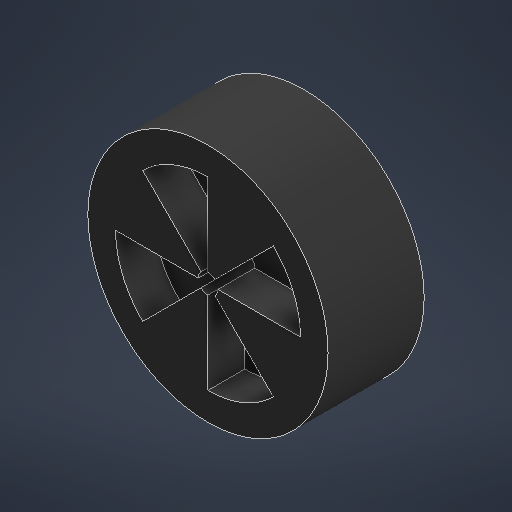
# Autodesk Inventor part: Rueda
Saved by Autodesk Inventor 2026.2 (Build 302298010, 298A)
## iProperties
Created: 2026-10-27
Part Number: Rueda
Material: Caucho
Document SubType Name: Modeling
Designer: efrey
Mass: 79.7032 g
Surface Area: 123.347 cm^2
Volume: 85.7024 cm^3
Density: 0.93 g/cm^3
Appearance: Caucho - Negro
Author: efrey
Autodesk Inventor part; units mm, degrees
ref_plane "YZ Plane" through (0, 0, 0) normal (1, 0, 0) x (0, 1, 0)
ref_plane "XZ Plane" through (0, 0, 0) normal (0, 1, 0) x (-1, 0, 0)
ref_plane "XY Plane" through (0, 0, 0) normal (0, 0, 1) x (1, 0, 0)
sketch "Boceto1" plane through (0, 0, 0) normal (0, 0, 1) x (1, 0, 0)
  circle A0 centre (0, 0) radius 32.5
  circle A1 centre (0, 0) radius 2.65
  dimension "d0" = 65
  dimension "d1" = 5.3
  constraints: 2 centre point, 2 coincident
  measures "d0" diameter of A0
  measures "d1" diameter of A1
extrude "Extrusión1" add sketch "Boceto1" along normal mid plane 26
sketch "Boceto2" plane through (0, 0, 13) normal (0, 0, 1) x (1, 0, 0)
  circle A0 centre (0, 0) radius 25
  circle A1 centre (0, 0) radius 2.65 projected
  line L0 (2.65, 0) -> (25, 0)
  line L1 (1.8738, 1.8738) -> (17.6777, 17.6777)
  line L2 (0, 0) -> (25, 0) construction
  line L3 (0, 2.65) -> (0, 25)
  line L4 (-1.8738, 1.8738) -> (-17.6777, 17.6777)
  line L5 (0, 0) -> (25, 0) construction
  line L6 (-2.65, 0) -> (-25, 0)
  line L7 (-1.8738, -1.8738) -> (-17.6777, -17.6777)
  line L8 (0, 0) -> (25, 0) construction
  line L9 (0, -2.65) -> (0, -25)
  line L10 (1.8738, -1.8738) -> (17.6777, -17.6777)
  line L11 (0, 0) -> (25, 0) construction
  circle A2 centre (0, 0) radius 2.65
  dimension "d4" = 50
  dimension "d5" = 45
  dimension "d6" = 135
  dimension "d7" = 135
  dimension "d8" = 45
  constraints: 24 end point, 6 horizontal, 2 coincident, 2 perpendicular, 21 other
  measures "d5" angle of L2 L1
  measures "d6" angle of L5 L4
  measures "d7" angle of L7 L8
  measures "d8" angle of L10 L11
extrude "Extrusión2" cut sketch "Boceto2" against normal blind 10 contours L0 A1 L1 A0 | A0 L9 A1 L10 | L3 A1 L4 A0 | A0 L6 A1 L7
